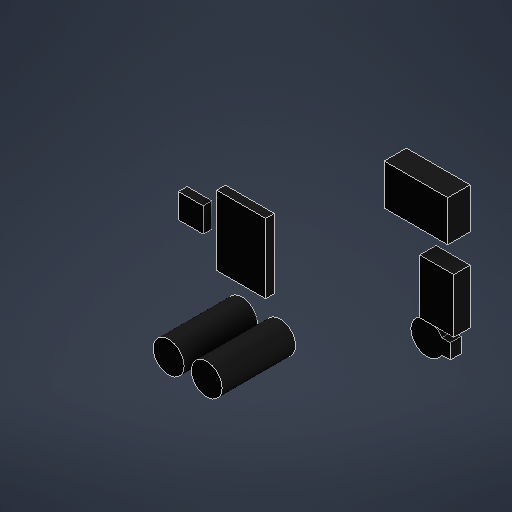
# Autodesk Inventor part: ref_parts
Saved by Autodesk Inventor 2027.1 (Build 311270010, 270A)
## iProperties
Created: 2026-10-22
Part Number: ref_parts
Material: 일반
Document SubType Name: Modeling
Designer: sungjun
Density: 1 g/cm^3
Appearance: ref_parts_c
Author: sungjun
Autodesk Inventor part; units mm, degrees
ref_plane "작업 평면1" through (0, 0, 48) normal (0, 0, 1) x (1, 0, 0)
sketch "스케치1" plane through (0, 0, 48) normal (0, 0, 1) x (1, 0, 0)
  circle A0 centre (49, 17.65) radius 5.7
  constraints: 1 centre point
extrude "돌출1" add sketch "스케치1" along normal mid plane 27
ref_plane "작업 평면2" through (0, 0, 48) normal (0, 0, 1) x (1, 0, 0)
sketch "스케치2" plane through (0, 0, 48) normal (0, 0, 1) x (1, 0, 0)
  circle A0 centre (63, 17.65) radius 5.7
  constraints: 1 centre point
extrude "돌출2" add sketch "스케치2" along normal mid plane 27
ref_plane "작업 평면3" through (0, 0, 9.7) normal (0, 0, 1) x (1, 0, 0)
sketch "스케치3" plane through (0, 0, 9.7) normal (0, 0, 1) x (1, 0, 0)
  line L0 (2.4, 13) -> (11.5, 13)
  line L1 (11.5, 13) -> (11.5, 22)
  line L2 (11.5, 22) -> (2.4, 22)
  line L3 (2.4, 22) -> (2.4, 13)
  constraints: 8 end point, 2 parallel, 1 horizontal, 1 perpendicular
extrude "돌출3" add sketch "스케치3" along normal mid plane 3.2
ref_plane "작업 평면4" through (0, 0, 12.2) normal (0, 0, 1) x (1, 0, 0)
sketch "스케치4" plane through (0, 0, 12.2) normal (0, 0, 1) x (1, 0, 0)
  line L0 (83.1, 59.6) -> (106.5, 59.6)
  line L1 (106.5, 59.6) -> (106.5, 74.6)
  line L2 (106.5, 74.6) -> (83.1, 74.6)
  line L3 (83.1, 74.6) -> (83.1, 59.6)
  constraints: 8 end point, 2 parallel, 1 horizontal, 1 perpendicular
extrude "돌출4" add sketch "스케치4" along normal mid plane 8.2
ref_plane "작업 평면5" through (0, 0, 11.1) normal (0, 0, 1) x (1, 0, 0)
sketch "스케치5" plane through (0, 0, 11.1) normal (0, 0, 1) x (1, 0, 0)
  line L0 (94, 29) -> (106.5, 29)
  line L1 (106.5, 29) -> (106.5, 49)
  line L2 (106.5, 49) -> (94, 49)
  line L3 (94, 49) -> (94, 29)
  constraints: 8 end point, 2 parallel, 1 horizontal, 1 perpendicular
extrude "돌출5" add sketch "스케치5" along normal mid plane 6
ref_plane "작업 평면6" through (0, 0, 9.7) normal (0, 0, 1) x (1, 0, 0)
sketch "스케치6" plane through (0, 0, 9.7) normal (0, 0, 1) x (1, 0, 0)
  line L0 (16.5, 3.9) -> (34.5, 3.9)
  line L1 (34.5, 3.9) -> (34.5, 29.5)
  line L2 (34.5, 29.5) -> (16.5, 29.5)
  line L3 (16.5, 29.5) -> (16.5, 3.9)
  constraints: 8 end point, 2 parallel, 1 horizontal, 1 perpendicular
extrude "돌출6" add sketch "스케치6" along normal mid plane 3.2
ref_plane "작업 평면7" through (0, 0, 10.1) normal (0, 0, 1) x (1, 0, 0)
sketch "스케치7" plane through (0, 0, 10.1) normal (0, 0, 1) x (1, 0, 0)
  circle A0 centre (94.7, 21.9) radius 6
  constraints: 1 centre point
extrude "돌출7" add sketch "스케치7" along normal mid plane 4
ref_plane "작업 평면8" through (0, 0, 10.1) normal (0, 0, 1) x (1, 0, 0)
sketch "스케치8" plane through (0, 0, 10.1) normal (0, 0, 1) x (1, 0, 0)
  line L0 (98.7, 19.15) -> (103.2, 19.15)
  line L1 (103.2, 19.15) -> (103.2, 24.65)
  line L2 (103.2, 24.65) -> (98.7, 24.65)
  line L3 (98.7, 24.65) -> (98.7, 19.15)
  constraints: 8 end point, 2 parallel, 1 horizontal, 1 perpendicular
extrude "돌출8" add sketch "스케치8" along normal mid plane 4
